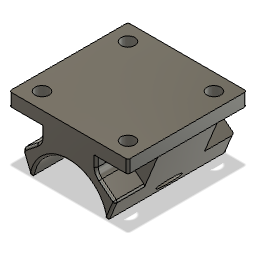
IMU_Thumb_Mount_01 v1 (Autodesk Fusion 360 design; units mm, degrees)
Autodesk Fusion 360 part; units mm, degrees
sketch "Sketch1" plane through (0, 0, 0) normal (0, 1, 0) x (1, 0, 0)
  line L0 (14, 14) -> (-14, 14)
  line L1 (-14, 14) -> (-14, -14)
  line L2 (-14, -14) -> (14, -14)
  line L3 (14, -14) -> (14, 14)
  line L4 (14, 14) -> (-14, -14) construction
  line L5 (-14, 14) -> (14, -14) construction
  line L6 (13, 13) -> (-13, 13) construction
  line L7 (-13, 13) -> (-13, -13) construction
  line L8 (-13, -13) -> (13, -13) construction
  line L9 (13, -13) -> (13, 13) construction
  line L10 (13, 13) -> (-13, -13) construction
  line L11 (-13, 13) -> (13, -13) construction
  line L12 (-10.125, 14) -> (-10.125, -14) construction
  line L13 (10.125, -14) -> (10.125, 14) construction
  line L14 (14, 10.125) -> (-14, 10.125) construction
  line L15 (-14, -10.125) -> (14, -10.125) construction
  circle A0 centre (10.125, 10.125) radius 1.625
  circle A1 centre (-10.125, 10.125) radius 1.625
  circle A2 centre (-10.125, -10.125) radius 1.625
  circle A3 centre (10.125, -10.125) radius 1.625
  dimension "d1" = 28
  dimension "d2" = 28
  dimension "d3" = 26
  dimension "d4" = 26
  dimension "d5" = 3.875
  dimension "d6" = 3.875
  dimension "d7" = 3.875
  dimension "d8" = 3.875
  dimension "d9" = 3.25
  dimension "d10" = 3.25
  dimension "d11" = 3.25
  dimension "d12" = 3.25
  constraint horizontal L0
  constraint perpendicular L0 L1
  constraint parallel L0 L2
  constraint parallel L1 L3
  constraint coincident L4 origin
  constraint coincident L5 origin
  constraint horizontal L6
  constraint perpendicular L6 L7
  constraint parallel L6 L8
  constraint parallel L7 L9
  constraint coincident L10 origin
  constraint coincident L11 origin
  constraint coincident L0 L12.start
  constraint coincident L2 L12.end
  constraint perpendicular L2 L12
  constraint coincident L2 L13.start
  constraint coincident L0 L13.end
  constraint perpendicular L0 L13
  constraint coincident L3 L14.start
  constraint perpendicular L3 L14
  constraint coincident L1 L14.end
  constraint coincident L1 L15.start
  constraint perpendicular L1 L15
  constraint coincident L3 L15.end
  constraint coincident L14 A0.centre
  constraint coincident L4 A0.centre
  constraint coincident L11 A1.centre
  constraint coincident L14 A1.centre
  constraint coincident L15 A2.centre
  constraint coincident L4 A2.centre
  constraint coincident L13 A3.centre
  constraint coincident L11 A3.centre
  measures "d1" distance of L1.end L2.end
  measures "d2" distance of L0.end L1.end
  measures "d3" distance of L7.end L8.end
  measures "d4" distance of L6.end L7.end
  measures "d5" distance of L3 L13
  measures "d6" distance of L1 L12
  measures "d7" distance of L2 L15
  measures "d8" distance of L0 L14
  measures "d9" diameter of A0
  measures "d10" diameter of A1
  measures "d11" diameter of A2
  measures "d12" diameter of A3
extrude "Extrude1" add sketch "Sketch1" along normal blind 3
sketch "Sketch2" plane through (0, 0, 0) normal (0, 0, 1) x (1, 0, 0)
  line L0 (0, 0) -> (0, -13) construction
  line L1 (0, 0) -> (0, -4.3333) construction
  circle A0 centre (0, -13) radius 8.6667
  line L2 (0, -13) -> (8.6667, -13)
  line L3 (0, -13) -> (-8.6667, -13)
  line L4 (-14, 0) -> (-8.6667, -13)
  line L5 (14, 0) -> (8.6667, -13)
  line L6 (-14, 0) -> (14, 0)
  line L7 (-8.5, 0) -> (-11.75, 0)
  line L8 (11.75, 0) -> (8.5, 0)
  line L9 (11.75, 0) -> (8.5, 0)
  line L10 (-8.5, 0) -> (-11.75, 0)
  line L11 (8.5, 0) -> (11.75, 0) construction
  line L12 (-8.5, 0) -> (-11.75, 0) construction
  line L13 (-8.5, 0) -> (-6.5, 0) construction
  line L14 (-11.75, 0) -> (-13.75, 0) construction
  line L15 (8.5, 0) -> (6.5, 0) construction
  line L16 (11.75, 0) -> (13.75, 0) construction
  line L17 (-6.5, 0) -> (-6.5, -7.2675)
  line L18 (6.5, 0) -> (6.5, -7.2675)
  line L19 (-6.5, -7.2675) -> (-11.0184, -7.2675)
  line L20 (6.5, -7.2675) -> (11.0184, -7.2675)
  line L21 (-11.0184, -7.2675) -> (-6.5, -3.6338)
  line L22 (11.0184, -7.2675) -> (6.5, -3.6338)
  dimension "d15" = 13
  dimension "d16" = 4.3333
  dimension "d17" = 2
  dimension "d18" = 2
  dimension "d19" = 2
  dimension "d20" = 2
  constraint vertical L0
  constraint coincident L0.start L1.start
  constraint parallel L0 L1
  constraint coincident L0.end A0.centre
  constraint coincident L1.end A0
  constraint coincident A0 L2.end
  constraint perpendicular L0 L2
  constraint coincident A0 L3.end
  constraint perpendicular L0 L3
  constraint horizontal L6
  constraint coincident L8.end L9.end
  constraint coincident L8.start L9.start
  constraint coincident L7.start L10.start
  constraint coincident L7.end L10.end
  constraint parallel L6 L13
  constraint parallel L6 L14
  constraint parallel L6 L15
  constraint parallel L6 L16
  constraint coincident A0 L17.end
  constraint perpendicular L13 L17
  constraint coincident A0 L18.end
  constraint perpendicular L15 L18
  constraint coincident L4 L19.end
  constraint perpendicular L17 L19
  constraint coincident L5 L20.end
  constraint perpendicular L18 L20
  constraint midpoint L17 L21.end
  constraint midpoint L18 L22.end
  measures "d15" distance of L0.start L0.end
  measures "d16" distance of L0.start L1.end
  measures "d17" distance of L7.start L13.end
  measures "d18" distance of L7.end L14.end
  measures "d19" distance of L8.end L15.end
  measures "d20" distance of L8.start L16.end
extrude "Extrude2" add sketch "Sketch2" along normal mid plane 28 contours A0 L6 L17 L18
extrude "Extrude3" add sketch "Sketch2" along normal mid plane 14 contours A0 L5 L20 | L18 L20 L22 | A0 L4 L19 | L5 L6 L8 L9 L18 L22 | L17 L19 L21 | L4 L6 L7 L10 L17 L21
sketch "Sketch3" plane through (0, 0, 0) normal (1, 0, 0) x (0, 0, -1)
  line L0 (7, -13) -> (-7, -13)
  line L1 (-7, -13) -> (-7, 0)
  line L2 (-7, 0) -> (7, 0)
  line L3 (7, 0) -> (7, -13)
  line L4 (7, 0) -> (-7, 0)
  line L5 (-7, 0) -> (-7, -13)
  line L6 (-7, -13) -> (7, -13)
  line L7 (7, -13) -> (7, 0)
  line L8 (-7, 0) -> (-7, -7.2675)
  line L9 (-7, -7.2675) -> (-14, -7.2675)
  line L10 (-14, -7.2675) -> (-14, 0)
  line L11 (-14, 0) -> (-7, 0)
  line L12 (7, -7.2675) -> (7, 0)
  line L13 (7, 0) -> (14, 0)
  line L14 (14, 0) -> (14, -7.2675)
  line L15 (14, -7.2675) -> (7, -7.2675)
  line L16 (7, 0) -> (7, -7.2675)
  line L17 (7, -7.2675) -> (14, -7.2675)
  line L18 (14, -7.2675) -> (14, 0)
  line L19 (14, 0) -> (7, 0)
  line L20 (-7, -7.2675) -> (-7, 0)
  line L21 (-7, 0) -> (-14, 0)
  line L22 (-14, 0) -> (-14, -7.2675)
  line L23 (-14, -7.2675) -> (-7, -7.2675)
  ellipse E0 centre (0, -10.5) end of major axis (-3.125, -10.5) minor radius 0.625
  line L24 (3.125, -10.5) -> (-3.125, -10.5) construction
  line L25 (0, -9.875) -> (0, -11.125) construction
  dimension "d25" = 6.25
  dimension "d26" = 1.25
  dimension "d29" = 2.5
  constraint coincident E0 L24.start
  constraint coincident E0 L24.end
  constraint coincident E0 L25.start
  constraint coincident E0 L25.end
  constraint parallel L6 L24
  measures "d25" distance of E0
  measures "d29" distance of L0 L24
extrude "Extrude5" add sketch "Sketch2" along normal mid plane 28 contours A0 L5 L20 | A0 L4 L19
extrude "Extrude6" add sketch "Sketch2" along normal mid plane 28 contours L18 L20 L22 | L17 L19 L21
extrude "Extrude7" cut sketch "Sketch3" along normal mid plane 22 contours E0
fillet "Fillet2" radius 0.33 2 edges at (-8.6667, -13, 0) (8.6667, -13, 0)
fillet "Fillet3" radius 2.5 4 edges at (-6.5, -3.6338, -10.5) (6.5, -3.6338, -10.5) (6.5, -3.6338, 10.5) (-6.5, -3.6338, 10.5)
fillet "Fillet4" radius 0.5 4 edges at (14, 1.5, 14) (14, 1.5, -14) (-14, 1.5, -14) (-14, 1.5, 14)
fillet "Fillet5" radius 0.5 9 edges at (-11.0184, -7.2675, -10.5) (-9.2259, -5.8259, -14) (-6.7454, -3.5162, -14) (-6.5, -1.2181, -14) (10.105, -9.494, -14) (8.848, -11.923, -14) (0, -4.3333, -14) (-8.848, -11.923, -14) (-10.105, -9.494, -14)
fillet "Fillet6" radius 0.5 9 edges at (-6.5, -1.2181, 14) (-6.7454, -3.5162, 14) (-9.2259, -5.8259, 14) (-11.0184, -7.2675, 10.5) (-10.105, -9.494, 14) (-8.848, -11.923, 14) (0, -4.3333, 14) (8.848, -11.923, 14) (10.105, -9.494, 14)
fillet "Fillet7" radius 0.5 5 edges at (11.0184, -7.2675, 10.25) (10.8994, -7.1718, 13.8536) (9.0227, -5.6625, 14) (6.7454, -3.5162, 14) (6.5, -1.2181, 14)
equation "d16 = ( 13 / 3 ) * 1 mm"
